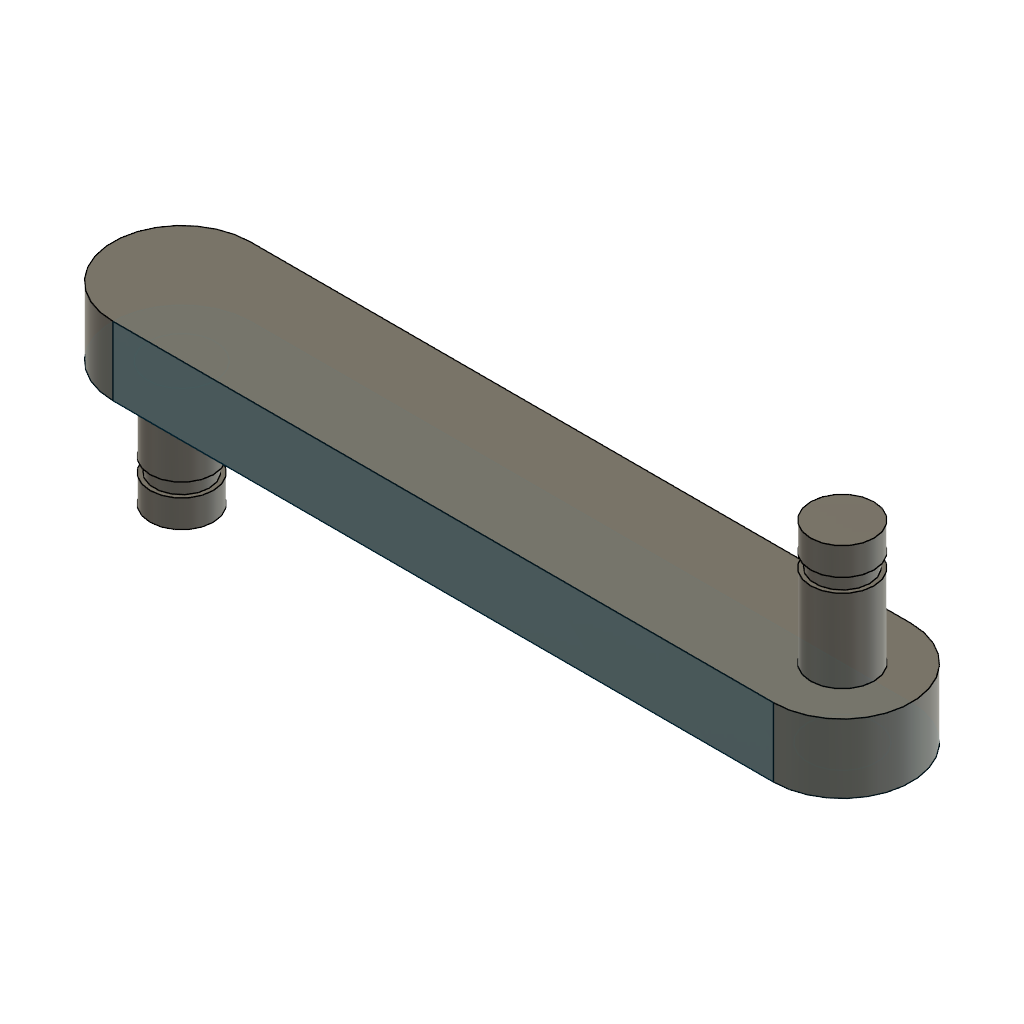
link 4,7 (Autodesk Fusion 360 design; units mm, degrees)
part number: 2026-11-18-20-16-01-248
Autodesk Fusion 360 part; units mm, degrees
sketch "Sketch1" plane through (0, 0, 0) normal (0, 1, 0) x (1, 0, 0)
  line L0 (0, -5) -> (48, -5)
  line L1 (0, 5) -> (48, 5)
  arc A0 (0, 5) -> (0, -5) centre (0, 0) ccw
  arc A1 (48, -5) -> (48, 5) centre (48, 0) ccw
  circle A2 centre (0, 0) radius 2.5
  circle A3 centre (48, 0) radius 2.5
  dimension "d1" = 10
  dimension "d2" = 48
  dimension "d3" = 5
  dimension "d4" = 10
  dimension "d5" = 5
  dimension "d6" = 5
  constraint coincident A0.centre A2.centre
  constraint horizontal L0
  constraint horizontal L1
  constraint concentric A0 A2
  constraint concentric A1 A3
  measures "d1" diameter of A0
  measures "d2" distance of L0.start L0.end
  measures "d3" distance of L0.end A1.centre
  measures "d4" distance of L0 L1
  measures "d5" diameter of A2
  measures "d6" diameter of A3
extrude "Extrude1" add sketch "Sketch1" along normal blind 5 makes body 1
sketch "Sketch2" plane through (0, 0, 5) normal (0, 0, 1) x (-1, 0, 0)
  line L0 (0, 0) -> (-48, 0)
  line L1 (-48, 0) -> (-48, -5)
  line L2 (-48, -5) -> (0, -5)
  line L3 (0, -5) -> (0, 0)
sketch "Sketch3" plane through (0, 0, 0) normal (0, -1, 0) x (1, 0, 0)
  circle A0 centre (48, 0) radius 2.5
  circle A1 centre (0, 0) radius 2.5
  arc A2 (0, 5) -> (0, -5) centre (0, 0) ccw
  line L0 (0, -5) -> (48, -5)
  arc A3 (48, -5) -> (48, 5) centre (48, 0) ccw
  line L1 (48, 5) -> (0, 5)
  circle A4 centre (0, 0) radius 2.5
  dimension "d9" = 5
  constraint coincident A1.centre A2.centre
  measures "d9" diameter of A4
extrude "Extrude2" add sketch "Sketch3" against normal blind 10 contours A1 A4 bodies 1
sketch "Sketch4" plane through (0, 10, 0) normal (0, 1, 0) x (-1, 0, 0)
  circle A0 centre (0, 0) radius 2.5
  circle A1 centre (0, 0) radius 2.45
  dimension "d12" = 4.9
  constraint concentric A0 A1
  measures "d12" diameter of A1
extrude "Extrude3" add sketch "Sketch4" along normal blind 1 contours A1 bodies 1
sketch "Sketch5" plane through (0, 11, 0) normal (0, 1, 0) x (-1, 0, 0)
  circle A0 centre (0, 0) radius 2.45
  circle A1 centre (0, 0) radius 2.5
  dimension "d15" = 5
  constraint coincident A0.centre A1.centre
  measures "d15" diameter of A1
extrude "Extrude4" add sketch "Sketch5" along normal blind 1 separate body makes body 2
extrude "Extrude5" add 1 faces at (0.5987, 11, 0.5555) along direction (0, 1, 0) blind 1 on bodies 1 bodies 1 2
extrude "Extrude6" cut 1 faces at (0.8863, 12, 0.2321) along direction (0, -1, 0) blind 23 on bodies 1 bodies 1
sketch "Sketch6" plane through (0, 5, 0) normal (0, 1, 0) x (-1, 0, 0)
  circle A0 centre (-48, 0) radius 2.5
  circle A1 centre (0, 0) radius 2.5
  arc A2 (0, -5) -> (0, 5) centre (0, 0) ccw
  line L0 (0, 5) -> (-48, 5)
  arc A3 (-48, 5) -> (-48, -5) centre (-48, 0) ccw
  line L1 (-48, -5) -> (0, -5)
  circle A4 centre (0, 0) radius 2.5
  dimension "d22" = 5
  constraint coincident A1.centre A2.centre
  measures "d22" diameter of A4
extrude "Extrude7" add sketch "Sketch6" against normal blind 10 contours A1 A4 bodies 1
sketch "Sketch7" plane through (0, -5, 0) normal (0, -1, 0) x (1, 0, 0)
  circle A0 centre (0, 0) radius 2.5
  circle A1 centre (0, 0) radius 2.45
  dimension "d25" = 4.9
  constraint coincident A0.centre A1.centre
  measures "d25" diameter of A1
extrude "Extrude8" cut sketch "Sketch7" against normal blind 5 bodies 1
sketch "Sketch8" plane through (0, -5, 0) normal (0, -1, 0) x (1, 0, 0)
  circle A0 centre (0, 0) radius 2.45
  circle A1 centre (0, 0) radius 2.4
  dimension "d28" = 4.8
  constraint coincident A0.centre A1.centre
  measures "d28" diameter of A1
extrude "Extrude9" add sketch "Sketch8" along normal blind 1 contours A1 bodies 1
sketch "Sketch9" plane through (0, -6, 0) normal (0, -1, 0) x (1, 0, 0)
  circle A0 centre (0, 0) radius 2.4
  circle A1 centre (0, 0) radius 2.45
  dimension "d31" = 4.9
  constraint coincident A0.centre A1.centre
  measures "d31" diameter of A1
extrude "Extrude10" add sketch "Sketch9" along normal blind 1 separate body makes body 3
extrude "Extrude11" add 1 faces at (0.4722, -6, 0.2704) along direction (0, -1, 0) blind 1 on bodies 1 bodies 1 3
sketch "Sketch10" plane through (0, 5, 0) normal (0, 1, 0) x (-1, 0, 0)
  circle A0 centre (-48, 0) radius 2.5
  arc A1 (0, -5) -> (0, 5) centre (0, 0) ccw
  line L0 (0, 5) -> (-48, 5)
  arc A2 (-48, 5) -> (-48, -5) centre (-48, 0) ccw
  line L1 (-48, -5) -> (0, -5)
  circle A3 centre (-48, 0) radius 2.5
  dimension "d36" = 5
  constraint concentric A0 A3
  measures "d36" diameter of A3
sketch "Sketch11" plane through (0, 0, 0) normal (0, -1, 0) x (1, 0, 0)
  circle A0 centre (0, 0) radius 2.45
  circle A1 centre (48, 0) radius 2.5
  arc A2 (0, 5) -> (0, -5) centre (0, 0) ccw
  line L0 (0, -5) -> (48, -5)
  arc A3 (48, -5) -> (48, 5) centre (48, 0) ccw
  line L1 (48, 5) -> (0, 5)
extrude "Extrude12" add sketch "Sketch10" along normal blind 5 separate body contours A0 A3 makes body 4
extrude "Extrude13" cut 1 faces at (48.7053, 10, -0.2456) along direction (0, -1, 0) blind 18 on bodies 4 bodies 4
sketch "Sketch12" plane through (0, 0, 0) normal (0, -1, 0) x (1, 0, 0)
  circle A0 centre (48, 0) radius 2.5
  dimension "d41" = 5
  measures "d41" diameter of A0
extrude "Extrude14" add sketch "Sketch12" against normal blind 10 bodies 1 4
sketch "Sketch13" plane through (0, 10, 0) normal (0, 1, 0) x (-1, 0, 0)
  circle A0 centre (-48, 0) radius 2.5
  circle A1 centre (-48, 0) radius 2.45
  dimension "d44" = 4.9
  constraint concentric A0 A1
  measures "d44" diameter of A1
extrude "Extrude15" cut sketch "Sketch13" against normal blind 5 bodies 1
sketch "Sketch14" plane through (0, 10, 0) normal (0, 1, 0) x (-1, 0, 0)
  circle A0 centre (-48, 0) radius 2.45
  circle A1 centre (-48, 0) radius 2.4
  dimension "d47" = 4.8
  constraint concentric A0 A1
  measures "d47" diameter of A1
extrude "Extrude16" add sketch "Sketch14" along normal blind 1 contours A1 bodies 1
sketch "Sketch15" plane through (0, 11, 0) normal (0, 1, 0) x (-1, 0, 0)
  circle A0 centre (-48, 0) radius 2.4
  circle A1 centre (-48, 0) radius 2.5
  dimension "d50" = 5
  constraint concentric A0 A1
  measures "d50" diameter of A1
extrude "Extrude17" add sketch "Sketch15" along normal blind 1 separate body makes body 5
extrude "Extrude18" add 1 faces at (48.178, 11, 0.7799) along direction (0, 1, 0) blind 1 on bodies 1 bodies 1 5
sketch "Sketch16" plane through (0, 0, 0) normal (0, -1, 0) x (1, 0, 0)
extrude "Extrude19" cut 1 faces at (-0.5987, -7, 0.5555) along direction (0, 1, 0) blind 2 on bodies 1 bodies 1
sketch "Sketch17" plane through (0, -5, 0) normal (0, -1, 0) x (1, 0, 0)
  circle A0 centre (0, 0) radius 2.45
  circle A1 centre (0, 0) radius 2.3
  dimension "d57" = 4.6
  constraint coincident A0.centre A1.centre
  measures "d57" diameter of A1
extrude "Extrude20" cut sketch "Sketch17" against normal blind 5 bodies 1
extrude "Extrude21" add 1 faces at (0.6334, -5, 0.6111) along direction (0, -1, 0) blind 1 on bodies 1 bodies 1
sketch "Sketch18" plane through (0, -6, 0) normal (0, -1, 0) x (1, 0, 0)
  circle A0 centre (0, 0) radius 2.3
  circle A1 centre (0, 0) radius 2
  dimension "d62" = 4
  constraint coincident A0.centre A1.centre
  measures "d62" diameter of A1
extrude "Extrude22" add sketch "Sketch18" along normal blind 1 contours A1 bodies 1
sketch "Sketch19" plane through (0, -7, 0) normal (0, -1, 0) x (1, 0, 0)
  circle A0 centre (0, 0) radius 2
  circle A1 centre (0, 0) radius 2.3
  dimension "d65" = 4.6
  constraint concentric A0 A1
  measures "d65" diameter of A1
extrude "Extrude23" add sketch "Sketch19" along normal blind 2 contours A0 | A1 bodies 1
sketch "Sketch20" plane through (0, 0, 0) normal (0, -1, 0) x (1, 0, 0)
sketch "Sketch21" plane through (0, 0, 5) normal (0, 0, 1) x (-1, 0, 0)
sketch "Sketch22" plane through (0, 12, 0) normal (0, 1, 0) x (-1, 0, 0)
  circle A0 centre (-48, 0) radius 2.5
extrude "Extrude24" cut sketch "Sketch22" against normal blind 2 bodies 1
sketch "Sketch23" plane through (0, 10, 0) normal (0, 1, 0) x (-1, 0, 0)
  circle A0 centre (-48, 0) radius 2.45
  circle A1 centre (-48, 0) radius 2.3
  dimension "d70" = 4.6
  constraint concentric A0 A1
  measures "d70" diameter of A1
extrude "Extrude25" cut sketch "Sketch23" against normal blind 5 bodies 1
extrude "Extrude26" add 1 faces at (48.0573, 10, -1.6283) along direction (0, 1, 0) blind 1 on bodies 1 bodies 1
sketch "Sketch24" plane through (0, 11, 0) normal (0, 1, 0) x (-1, 0, 0)
  circle A0 centre (-48, 0) radius 2.3
  circle A1 centre (-48, 0) radius 2
  dimension "d75" = 4
  constraint concentric A0 A1
  measures "d75" diameter of A1
extrude "Extrude27" add sketch "Sketch24" along normal blind 1 contours A1 bodies 1
sketch "Sketch25" plane through (0, 0, 0) normal (0, -1, 0) x (1, 0, 0)
sketch "Sketch26" plane through (0, 12, 0) normal (0, 1, 0) x (-1, 0, 0)
  circle A0 centre (-48, 0) radius 2
  circle A1 centre (-48, 0) radius 2.3
  dimension "d78" = 4.6
  constraint concentric A0 A1
  measures "d78" diameter of A1
extrude "Extrude28" add sketch "Sketch26" along normal blind 2 contours A0 | A1 bodies 1
sketch "Sketch27" plane through (0, 0, 5) normal (0, 0, 1) x (-1, 0, 0)
